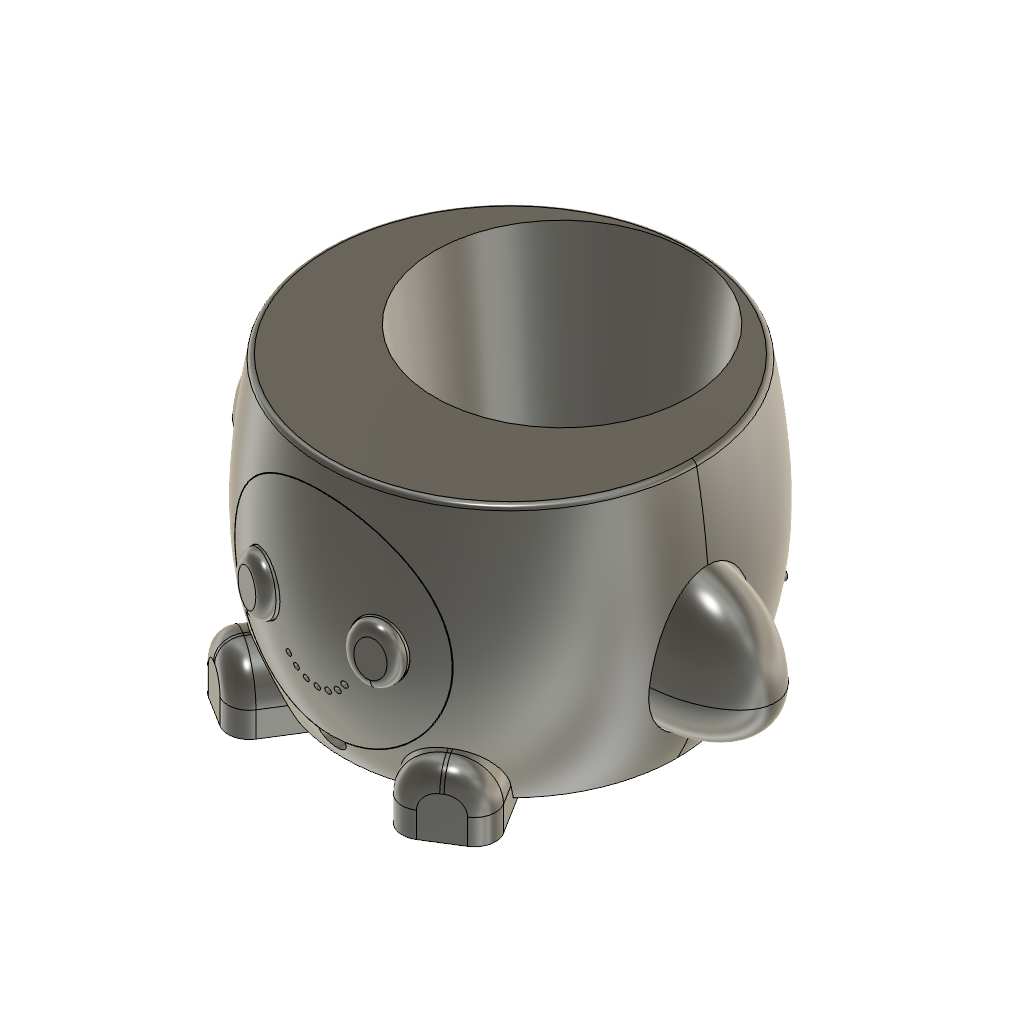
futamaru_pot (Autodesk Fusion 360 design; units mm, degrees)
Autodesk Fusion 360 part; units mm, degrees
(part 1 of 2)
sketch "スケッチ1" plane through (0, 0, 0) normal (0, 1, 0) x (1, 0, 0) in component "本体"
  spline S0 degree 5 poles (61, 0) (61.4755, -0.7477) (62.4092, -2.2714) (63.7579, -4.6416) (65.4521, -7.9718) (67.3928, -12.4202) (69.1495, -17.1541) (70.7118, -22.1673) (72.0655, -27.4438) (73.1935, -32.9563) (74.0795, -38.6683) (74.7115, -44.5354) (75.0851, -50.5067) (75.208, -56.5257) (75.1035, -62.5308) (74.8044, -68.4599) (74.349, -74.2534) (73.7756, -79.8585) (73.1181, -85.2326) (72.4013, -90.349) (71.6398, -95.1953) (71.0009, -98.8533) (70.5064, -101.4742) (70.1699, -103.1671) (70, -104) knots 0 0 0 0 0 0 0.05 0.1 0.15 0.2 0.25 0.3 0.35 0.4 0.45 0.5 0.55 0.6 0.65 0.7 0.75 0.8 0.85 0.9 0.95 1 1 1 1 1 1
  line L0 (0, 0) -> (61, 0)
  line L1 (70, -104) -> (0, -104)
  line L2 (0, -104) -> (0, 0)
  point P0 (70, -20)
  point P1 (75, -50)
  point P2 (73.5, -82)
  dimension "d76" = 61
  dimension "d77" = 70
  dimension "d78" = 20
  dimension "d79" = 75
  dimension "d80" = 50
  dimension "d81" = 73.5
  dimension "d82" = 82
  dimension "d83" = 70
  dimension "d84" = 104
  constraint horizontal L0
  constraint horizontal L1
  constraint vertical L2
  measures "d76" distance of L0.start S0.start
  measures "d77" horizontal distance of L0.start P0
  measures "d78" vertical distance of L0.start P0
  measures "d79" horizontal distance of L0.start P1
  measures "d80" vertical distance of L0.start P1
  measures "d81" horizontal distance of L0.start P2
  measures "d82" vertical distance of L0.start P2
  measures "d83" distance of L0.start S0.end
  measures "d84" distance of L0.start S0.end
revolve "本体 (1)" add sketch "スケッチ1" angle 360 about axis through (0, 0, 104) along (0, 0, -1) makes body 1 in component "本体"
chamfer "本体_底の面取り" distance 4 angle 45 1 edges at (-56.872, -22.0585, 0) tangent chain off on bodies 1 in component "本体"
fillet "本体_上の丸み" radius 2 1 edges at (-65.2629, -25.3131, 104) on bodies 1 in component "本体"
ref_plane "作業平面1" through (0, 0, 14) normal (0, 0, 1) x (1, 0, 0) in component "本体"
sketch "スケッチ2" plane through (0, 0, 14) normal (0, 0, 1) x (1, 0, 0) in component "本体"
  circle A0 centre (0, 19.5) radius 37
  line L0 (0, 0) -> (0, 10) construction
  dimension "d91" = 74
  dimension "d92" = 19.5
  constraint vertical L0
  constraint coincident A0.centre L0
  measures "d91" diameter of A0
  measures "d92" vertical distance of L0.start A0.centre
ref_plane "作業平面2" through (0, 0, 106) normal (0, 0, 1) x (1, 0, 0) in component "本体"
sketch "スケッチ3" plane through (0, 0, 106) normal (0, 0, 1) x (1, 0, 0) in component "本体"
  circle A0 centre (0, 19.5) radius 48.2444
  line L0 (0, 0) -> (0, 10) construction
  dimension "d95" = 96.4889
  dimension "d96" = 19.5
  constraint vertical L0
  constraint coincident A0.centre L0
  measures "d95" diameter of A0
  measures "d96" vertical distance of L0.start A0.centre
loft "鉢の穴" cut profiles "スケッチ2", "スケッチ3" section 1 section 2 bodies 1 in component "本体"
sketch "スケッチ4" plane through (0, 0, 14) normal (0, 0, 1) x (1, 0, 0) in component "本体"
  circle A0 centre (0, 41.5) radius 4
  line L0 (0, 0) -> (0, 10) construction
  circle A1 centre (-19.052, 8.5) radius 4
  circle A2 centre (19.052, 8.5) radius 4
  dimension "d97" = 8
  dimension "d98" = 41.5
  dimension "d99" = 8
  dimension "d100" = 19.052
  dimension "d101" = 8.5
  dimension "d102" = 8
  dimension "d103" = 19.052
  dimension "d104" = 8.5
  constraint vertical L0
  constraint coincident A0.centre L0
  measures "d97" diameter of A0
  measures "d98" vertical distance of L0.start A0.centre
  measures "d99" diameter of A1
  measures "d100" horizontal distance of L0.start A1.centre
  measures "d101" vertical distance of L0.start A1.centre
  measures "d102" diameter of A2
  measures "d103" horizontal distance of L0.start A2.centre
  measures "d104" vertical distance of L0.start A2.centre
extrude "鉢を浮かせる突起 (1)" add sketch "スケッチ4" along normal blind 3 bodies 1 in component "本体"
ref_plane "作業平面3" through (0, -90.5, 0) normal (0, 1, 0) x (0, 0, 1) in component "本体"
sketch "スケッチ5" plane through (0, -90.5, 0) normal (0, 1, 0) x (1, 0, 0) in component "本体"
  circle A0 centre (0, -54) radius 41.2
  line L0 (0, 0) -> (0, -10) construction
  dimension "d109" = 82.4
  dimension "d110" = 54
  constraint vertical L0
  constraint coincident A0.centre L0
  measures "d109" diameter of A0
  measures "d110" vertical distance of L0.start A0.centre
extrude "顔のふたの穴 (1)" cut sketch "スケッチ5" along normal blind 32 bodies 1 in component "本体"
ref_plane "作業平面4" through (0, -58.5, 0) normal (0, 1, 0) x (0, 0, 1) in component "本体"
sketch "スケッチ6" plane through (0, -58.5, 0) normal (0, 1, 0) x (1, 0, 0) in component "本体"
  circle A0 centre (0, -54) radius 39
  line L0 (0, 0) -> (0, -10) construction
  dimension "d115" = 78
  dimension "d116" = 54
  constraint vertical L0
  constraint coincident A0.centre L0
  measures "d115" diameter of A0
  measures "d116" vertical distance of L0.start A0.centre
extrude "部屋 (1)" cut sketch "スケッチ6" along normal blind 28 bodies 1 in component "本体"
sketch "スケッチ7" plane through (0, -90.5, 0) normal (0, 1, 0) x (1, 0, 0) in component "本体"
  circle A0 centre (0, -13) radius 5
  line L0 (0, 0) -> (0, -10) construction
  dimension "d119" = 10
  dimension "d120" = 13
  constraint vertical L0
  constraint coincident A0.centre L0
  measures "d119" diameter of A0
  measures "d120" vertical distance of L0.start A0.centre
extrude "指かけ (1)" cut sketch "スケッチ7" along normal blind 32 bodies 1 in component "本体"
sketch "スケッチ8" plane through (0, -58.5, 0) normal (0, 1, 0) x (1, 0, 0) in component "本体"
  circle A0 centre (34, -54) radius 6
  circle A1 centre (-34, -54) radius 6
  circle A2 centre (24, -30) radius 6
  circle A3 centre (-24, -30) radius 6
  dimension "d123" = 12
  dimension "d124" = 34
  dimension "d125" = 54
  dimension "d126" = 12
  dimension "d127" = 34
  dimension "d128" = 12
  dimension "d129" = 24
  dimension "d130" = 30
  dimension "d131" = 12
  dimension "d132" = 24
  dimension "d133" = 30
  measures "d123" diameter of A0
  measures "d124" horizontal distance of origin A0.centre
  measures "d125" vertical distance of origin A0.centre
  measures "d126" diameter of A1
  measures "d127" horizontal distance of origin A1.centre
  measures "d128" diameter of A2
  measures "d129" horizontal distance of origin A2.centre
  measures "d130" vertical distance of origin A2.centre
  measures "d131" diameter of A3
  measures "d132" horizontal distance of origin A3.centre
  measures "d133" vertical distance of origin A3.centre
extrude "磁石のボス (1)" add sketch "スケッチ8" along normal blind 5.5 bodies 1 in component "本体"
sketch "スケッチ9" plane through (0, -58.5, 0) normal (0, 1, 0) x (1, 0, 0) in component "本体"
  circle A0 centre (34, -54) radius 3.1
  circle A1 centre (-34, -54) radius 3.1
  circle A2 centre (24, -30) radius 3.1
  circle A3 centre (-24, -30) radius 3.1
  dimension "d136" = 6.2
  dimension "d137" = 34
  dimension "d138" = 54
  dimension "d139" = 6.2
  dimension "d140" = 34
  dimension "d141" = 6.2
  dimension "d142" = 24
  dimension "d143" = 30
  dimension "d144" = 6.2
  dimension "d145" = 24
  dimension "d146" = 30
  measures "d136" diameter of A0
  measures "d137" horizontal distance of origin A0.centre
  measures "d138" vertical distance of origin A0.centre
  measures "d139" diameter of A1
  measures "d140" horizontal distance of origin A1.centre
  measures "d141" diameter of A2
  measures "d142" horizontal distance of origin A2.centre
  measures "d143" vertical distance of origin A2.centre
  measures "d144" diameter of A3
  measures "d145" horizontal distance of origin A3.centre
  measures "d146" vertical distance of origin A3.centre
extrude "磁石の穴 (1)" cut sketch "スケッチ9" along normal blind 3.1 bodies 1 in component "本体"
ref_plane "作業平面5" through (0, 0, 29) normal (0, 0, 1) x (1, 0, 0) in component "本体"
sketch "スケッチ10" plane through (0, 0, 29) normal (0, 0, 1) x (1, 0, 0) in component "本体"
  line L0 (-13.5, -58.3) -> (13.5, -58.3)
  line L1 (13.5, -58.3) -> (13.5, -30.5)
  line L2 (13.5, -30.5) -> (-13.5, -30.5)
  line L3 (-13.5, -30.5) -> (-13.5, -58.3)
  dimension "d151" = 13.5
  dimension "d152" = 13.5
  dimension "d153" = 58.3
  dimension "d154" = 30.5
  measures "d151" horizontal distance of origin L0.start
  measures "d152" horizontal distance of origin L1.end
  measures "d153" vertical distance of origin L0.start
  measures "d154" vertical distance of origin L1.end
extrude "Voice Baseの台 (1)" add sketch "スケッチ10" against normal blind 20 bodies 1 in component "本体"
sketch "スケッチ11" plane through (0, 0, 29) normal (0, 0, 1) x (1, 0, 0) in component "本体"
  line L0 (-13.5, -58.3) -> (-12.3, -58.3)
  line L1 (-12.3, -58.3) -> (-12.3, -30.5)
  line L2 (-12.3, -30.5) -> (-13.5, -30.5)
  line L3 (-13.5, -30.5) -> (-13.5, -58.3)
  line L4 (12.3, -58.3) -> (13.5, -58.3)
  line L5 (13.5, -58.3) -> (13.5, -30.5)
  line L6 (13.5, -30.5) -> (12.3, -30.5)
  line L7 (12.3, -30.5) -> (12.3, -58.3)
  line L8 (-6, -34) -> (6, -34)
  line L9 (6, -34) -> (6, -30.5)
  line L10 (6, -30.5) -> (-6, -30.5)
  line L11 (-6, -30.5) -> (-6, -34)
  dimension "d157" = 13.5
  dimension "d158" = 12.3
  dimension "d159" = 58.3
  dimension "d160" = 30.5
  dimension "d161" = 12.3
  dimension "d162" = 13.5
  dimension "d163" = 30.5
  dimension "d164" = 6
  dimension "d165" = 6
  dimension "d166" = 34
  dimension "d167" = 30.5
  measures "d157" horizontal distance of origin L0.start
  measures "d158" horizontal distance of origin L1.end
  measures "d159" vertical distance of origin L0.start
  measures "d160" vertical distance of origin L1.end
  measures "d161" horizontal distance of origin L4.start
  measures "d162" horizontal distance of origin L5.end
  measures "d163" vertical distance of origin L5.end
  measures "d164" horizontal distance of origin L8.start
  measures "d165" horizontal distance of origin L9.end
  measures "d166" vertical distance of origin L8.start
  measures "d167" vertical distance of origin L9.end
extrude "Voice Baseの縁 (1)" add sketch "スケッチ11" along normal blind 4 bodies 1 in component "本体"
ref_plane "作業平面6" through (0, -30.5, 0) normal (0, 1, 0) x (0, 0, 1) in component "本体"
sketch "スケッチ12" plane through (0, -30.5, 0) normal (0, 1, 0) x (1, 0, 0) in component "本体"
  line L0 (12.1, -35.5) -> (13.3, -35.5)
  line L1 (13.3, -35.5) -> (13.3, -59.5)
  line L2 (13.3, -59.5) -> (12.1, -59.5)
  line L3 (12.1, -59.5) -> (12.1, -35.5)
  line L4 (31.7, -35.5) -> (32.9, -35.5)
  line L5 (32.9, -35.5) -> (32.9, -59.5)
  line L6 (32.9, -59.5) -> (31.7, -59.5)
  line L7 (31.7, -59.5) -> (31.7, -35.5)
  line L8 (12.1, -58.3) -> (32.9, -58.3)
  line L9 (32.9, -58.3) -> (32.9, -59.5)
  line L10 (32.9, -59.5) -> (12.1, -59.5)
  line L11 (12.1, -59.5) -> (12.1, -58.3)
  line L12 (12.1, -35.5) -> (15.75, -35.5)
  line L13 (15.75, -35.5) -> (15.75, -36.7)
  line L14 (15.75, -36.7) -> (12.1, -36.7)
  line L15 (12.1, -36.7) -> (12.1, -35.5)
  line L16 (29.25, -35.5) -> (32.9, -35.5)
  line L17 (32.9, -35.5) -> (32.9, -36.7)
  line L18 (32.9, -36.7) -> (29.25, -36.7)
  line L19 (29.25, -36.7) -> (29.25, -35.5)
  dimension "d172" = 12.1
  dimension "d173" = 13.3
  dimension "d174" = 35.5
  dimension "d175" = 59.5
  dimension "d176" = 31.7
  dimension "d177" = 32.9
  dimension "d178" = 59.5
  dimension "d179" = 32.9
  dimension "d180" = 58.3
  dimension "d181" = 59.5
  dimension "d182" = 15.75
  dimension "d183" = 36.7
  dimension "d184" = 29.25
  dimension "d185" = 32.9
  dimension "d186" = 36.7
  measures "d172" horizontal distance of origin L0.start
  measures "d173" horizontal distance of origin L1.end
  measures "d174" vertical distance of origin L0.start
  measures "d175" vertical distance of origin L1.end
  measures "d176" horizontal distance of origin L4.start
  measures "d177" horizontal distance of origin L5.end
  measures "d178" vertical distance of origin L5.end
  measures "d179" horizontal distance of origin L5.end
  measures "d180" vertical distance of origin L8.start
  measures "d181" vertical distance of origin L5.end
  measures "d182" horizontal distance of origin L13.end
  measures "d183" vertical distance of origin L13.end
  measures "d184" horizontal distance of origin L16.start
  measures "d185" horizontal distance of origin L17.end
  measures "d186" vertical distance of origin L17.end
extrude "XIAOの枠 (1)" add sketch "スケッチ12" against normal blind 5.2 bodies 1 in component "本体"
ref_plane "作業平面7" through (0, 0, -1) normal (0, 0, 1) x (1, 0, 0) in component "本体"
sketch "スケッチ13" plane through (0, 0, -1) normal (0, 0, 1) x (1, 0, 0) in component "本体"
  line L0 (15.5, -36.9) -> (29.5, -36.9)
  line L1 (29.5, -36.9) -> (29.5, -26.9)
  line L2 (29.5, -26.9) -> (15.5, -26.9)
  line L3 (15.5, -26.9) -> (15.5, -36.9)
  dimension "d191" = 15.5
  dimension "d192" = 29.5
  dimension "d193" = 36.9
  dimension "d194" = 26.9
  measures "d191" horizontal distance of origin L0.start
  measures "d192" horizontal distance of origin L1.end
  measures "d193" vertical distance of origin L0.start
  measures "d194" vertical distance of origin L1.end
extrude "USBケーブルの縦の穴 (1)" cut sketch "スケッチ13" along normal blind 46.3 bodies 1 in component "本体"
ref_plane "作業平面8" through (0, -31.9, 0) normal (0, 1, 0) x (0, 0, 1) in component "本体"
sketch "スケッチ14" plane through (0, -31.9, 0) normal (0, 1, 0) x (1, 0, 0) in component "本体"
  line L0 (19, 1) -> (26, 1)
  line L1 (26, 1) -> (26, -4.5)
  line L2 (26, -4.5) -> (22.5, -8)
  line L3 (22.5, -8) -> (19, -4.5)
  line L4 (19, -4.5) -> (19, 1)
extrude "USBケーブルの底の溝 (1)" cut sketch "スケッチ14" along normal blind 111.9 bodies 1 in component "本体"
ref_plane "作業平面1" through (0, -90.5, 0) normal (0, 1, 0) x (0, 0, 1) in component "顔のふた"
sketch "スケッチ1 (2)" plane through (0, -90.5, 0) normal (0, 1, 0) x (1, 0, 0) in component "顔のふた"
  circle A0 centre (0, -54) radius 41
  line L0 (0, 0) -> (0, -10) construction
  dimension "d203" = 82
  dimension "d204" = 54
  constraint vertical L0
  constraint coincident A0.centre L0
  measures "d203" diameter of A0
  measures "d204" vertical distance of L0.start A0.centre
extrude "顔のふた_外形 (1)" add sketch "スケッチ1 (2)" along normal blind 32 separate body makes body 2 in component "顔のふた"
sketch "スケッチ2 (2)" plane through (0, 0, 0) normal (0, 1, 0) x (1, 0, 0) in component "顔のふた"
  spline S0 degree 5 poles (61, 0) (61.4755, -0.7477) (62.4092, -2.2714) (63.7579, -4.6416) (65.4521, -7.9718) (67.3928, -12.4202) (69.1495, -17.1541) (70.7118, -22.1673) (72.0655, -27.4438) (73.1935, -32.9563) (74.0795, -38.6683) (74.7115, -44.5354) (75.0851, -50.5067) (75.208, -56.5257) (75.1035, -62.5308) (74.8044, -68.4599) (74.349, -74.2534) (73.7756, -79.8585) (73.1181, -85.2326) (72.4013, -90.349) (71.6398, -95.1953) (71.0009, -98.8533) (70.5064, -101.4742) (70.1699, -103.1671) (70, -104) knots 0 0 0 0 0 0 0.05 0.1 0.15 0.2 0.25 0.3 0.35 0.4 0.45 0.5 0.55 0.6 0.65 0.7 0.75 0.8 0.85 0.9 0.95 1 1 1 1 1 1
  line L0 (0, 0) -> (61, 0)
  line L1 (70, -104) -> (0, -104)
  line L2 (0, -104) -> (0, 0)
  point P0 (70, -20)
  point P1 (75, -50)
  point P2 (73.5, -82)
  constraint horizontal L0
  constraint horizontal L1
  constraint vertical L2
revolve "顔のふた_削り型 (1)" add sketch "スケッチ2 (2)" angle 360 about axis through (0, 0, 104) along (0, 0, -1) separate body makes body 3 in component "顔のふた"
chamfer "顔のふた_削り型_底の面取り" distance 4 angle 45 1 edges at (-56.872, -22.0585, 0) tangent chain off on bodies 3 in component "顔のふた"
fillet "顔のふた_削り型_上の丸み" radius 2 1 edges at (-65.2629, -25.3131, 104) on bodies 3 in component "顔のふた"
combine "顔のふた_本体の曲面で切る" operation intersect target body 2 tool bodies 3 in component "顔のふた"
ref_plane "作業平面2" through (0, -58.5, 0) normal (0, 1, 0) x (0, 0, 1) in component "顔のふた"
sketch "スケッチ3 (2)" plane through (0, -58.5, 0) normal (0, 1, 0) x (1, 0, 0) in component "顔のふた"
  line L0 (-14.1, -29.9) -> (14.1, -29.9)
  line L1 (14.1, -29.9) -> (14.1, -39.5)
  line L2 (14.1, -39.5) -> (-14.1, -39.5)
  line L3 (-14.1, -39.5) -> (-14.1, -29.9)
  dimension "d213" = 14.1
  dimension "d214" = 14.1
  dimension "d215" = 29.9
  dimension "d216" = 39.5
  measures "d213" horizontal distance of origin L0.start
  measures "d214" horizontal distance of origin L1.end
  measures "d215" vertical distance of origin L0.start
  measures "d216" vertical distance of origin L1.end
extrude "口の奥の音の部屋 (1)" cut sketch "スケッチ3 (2)" against normal blind 10.5 bodies 2 in component "顔のふた"
ref_plane "作業平面3" through (0, -68.5, 0) normal (0, 1, 0) x (0, 0, 1) in component "顔のふた"
sketch "スケッチ4 (2)" plane through (0, -68.5, 0) normal (0, 1, 0) x (1, 0, 0) in component "顔のふた"
  circle A0 centre (-10.5, -37.7) radius 1.2
  circle A1 centre (-7.7784, -34.505) radius 1.2
  circle A2 centre (-4.1344, -32.4227) radius 1.2
  circle A3 centre (0, -31.7) radius 1.2
  line L0 (0, 0) -> (0, -10) construction
  circle A4 centre (4.1344, -32.4227) radius 1.2
  circle A5 centre (7.7784, -34.505) radius 1.2
  circle A6 centre (10.5, -37.7) radius 1.2
  dimension "d221" = 2.4
  dimension "d222" = 10.5
  dimension "d223" = 37.7
  dimension "d224" = 2.4
  dimension "d225" = 7.7784
  dimension "d226" = 34.505
  dimension "d227" = 2.4
  dimension "d228" = 4.1344
  dimension "d229" = 32.4227
  dimension "d230" = 2.4
  dimension "d231" = 31.7
  dimension "d232" = 2.4
  dimension "d233" = 4.1344
  dimension "d234" = 32.4227
  dimension "d235" = 2.4
  dimension "d236" = 7.7784
  dimension "d237" = 34.505
  dimension "d238" = 2.4
  dimension "d239" = 10.5
  constraint vertical L0
  constraint coincident A3.centre L0
  measures "d221" diameter of A0
  measures "d222" horizontal distance of L0.start A0.centre
  measures "d223" vertical distance of L0.start A0.centre
  measures "d224" diameter of A1
  measures "d225" horizontal distance of L0.start A1.centre
  measures "d226" vertical distance of L0.start A1.centre
  measures "d227" diameter of A2
  measures "d228" horizontal distance of L0.start A2.centre
  measures "d229" vertical distance of L0.start A2.centre
  measures "d230" diameter of A3
  measures "d231" vertical distance of L0.start A3.centre
  measures "d232" diameter of A4
  measures "d233" horizontal distance of L0.start A4.centre
  measures "d234" vertical distance of L0.start A4.centre
  measures "d235" diameter of A5
  measures "d236" horizontal distance of L0.start A5.centre
  measures "d237" vertical distance of L0.start A5.centre
  measures "d238" diameter of A6
  measures "d239" horizontal distance of L0.start A6.centre
extrude "口 (1)" cut sketch "スケッチ4 (2)" against normal blind 20 bodies 2 in component "顔のふた"
sketch "スケッチ5 (2)" plane through (0, -58.5, 0) normal (0, 1, 0) x (1, 0, 0) in component "顔のふた"
  circle A0 centre (34, -54) radius 3.1
  circle A1 centre (-34, -54) radius 3.1
  circle A2 centre (24, -30) radius 3.1
  circle A3 centre (-24, -30) radius 3.1
  dimension "d242" = 6.2
  dimension "d243" = 34
  dimension "d244" = 54
  dimension "d245" = 6.2
  dimension "d246" = 34
  dimension "d247" = 6.2
  dimension "d248" = 24
  dimension "d249" = 30
  dimension "d250" = 6.2
  dimension "d251" = 24
  dimension "d252" = 30
  measures "d242" diameter of A0
  measures "d243" horizontal distance of origin A0.centre
  measures "d244" vertical distance of origin A0.centre
  measures "d245" diameter of A1
  measures "d246" horizontal distance of origin A1.centre
  measures "d247" diameter of A2
  measures "d248" horizontal distance of origin A2.centre
  measures "d249" vertical distance of origin A2.centre
  measures "d250" diameter of A3
  measures "d251" horizontal distance of origin A3.centre
  measures "d252" vertical distance of origin A3.centre
extrude "磁石の穴 (1)'" cut sketch "スケッチ5 (2)" against normal blind 3.1 bodies 2 in component "顔のふた"
ref_plane "作業平面1" through (0, -58.3, 0) normal (0, 1, 0) x (0, 0, 1) in component "参照部品（印刷しない）"
sketch "スケッチ1 (3)" plane through (0, -58.3, 0) normal (0, 1, 0) x (1, 0, 0) in component "参照部品（印刷しない）"
  line L0 (-12, -29) -> (12, -29)
  line L1 (12, -29) -> (12, -39)
  line L2 (12, -39) -> (-12, -39)
  line L3 (-12, -39) -> (-12, -29)
  dimension "d257" = 12
  dimension "d258" = 12
  dimension "d259" = 29
  dimension "d260" = 39
  measures "d257" horizontal distance of origin L0.start
  measures "d258" horizontal distance of origin L1.end
  measures "d259" vertical distance of origin L0.start
  measures "d260" vertical distance of origin L1.end
extrude "参照_Voice Base (1)" add sketch "スケッチ1 (3)" along normal blind 24 separate body makes body 4 in component "参照部品（印刷しない）"
ref_plane "作業平面2" through (0, 0, 39) normal (0, 0, 1) x (1, 0, 0) in component "参照部品（印刷しない）"
sketch "スケッチ2 (3)" plane through (0, 0, 39) normal (0, 0, 1) x (1, 0, 0) in component "参照部品（印刷しない）"
  line L0 (-3.78, -55.22) -> (8.92, -55.22)
  line L1 (8.92, -55.22) -> (8.92, -52.68)
  line L2 (8.92, -52.68) -> (-3.78, -52.68)
  line L3 (-3.78, -52.68) -> (-3.78, -55.22)
  dimension "d265" = 3.78
  dimension "d266" = 8.92
  dimension "d267" = 55.22
  dimension "d268" = 52.68
  measures "d265" horizontal distance of origin L0.start
  measures "d266" horizontal distance of origin L1.end
  measures "d267" vertical distance of origin L0.start
  measures "d268" vertical distance of origin L1.end
extrude "参照_Voice Baseのコネクタ (1)" add sketch "スケッチ2 (3)" along normal blind 14 separate body makes body 5 in component "参照部品（印刷しない）"
sketch "スケッチ3 (3)" plane through (0, 0, 39) normal (0, 0, 1) x (1, 0, 0) in component "参照部品（印刷しない）"
  line L0 (-1.24, -39.92) -> (8.92, -39.92)
  line L1 (8.92, -39.92) -> (8.92, -37.38)
  line L2 (8.92, -37.38) -> (-1.24, -37.38)
  line L3 (-1.24, -37.38) -> (-1.24, -39.92)
  dimension "d271" = 1.24
  dimension "d272" = 8.92
  dimension "d273" = 39.92
  dimension "d274" = 37.38
  measures "d271" horizontal distance of origin L0.start
  measures "d272" horizontal distance of origin L1.end
  measures "d273" vertical distance of origin L0.start
  measures "d274" vertical distance of origin L1.end
extrude "参照_Voice Baseのコネクタ (2)" add sketch "スケッチ3 (3)" along normal blind 14 separate body makes body 6 in component "参照部品（印刷しない）"
ref_plane "作業平面3" through (0, -33.5, 0) normal (0, 1, 0) x (0, 0, 1) in component "参照部品（印刷しない）"
sketch "スケッチ4 (3)" plane through (0, -33.5, 0) normal (0, 1, 0) x (1, 0, 0) in component "参照部品（印刷しない）"
  line L0 (13.6, -37) -> (31.4, -37)
  line L1 (31.4, -37) -> (31.4, -58)
  line L2 (31.4, -58) -> (13.6, -58)
  line L3 (13.6, -58) -> (13.6, -37)
  dimension "d279" = 13.6
  dimension "d280" = 31.4
  dimension "d281" = 37
  dimension "d282" = 58
  measures "d279" horizontal distance of origin L0.start
  measures "d280" horizontal distance of origin L1.end
  measures "d281" vertical distance of origin L0.start
  measures "d282" vertical distance of origin L1.end
extrude "参照_XIAO (1)" add sketch "スケッチ4 (3)" against normal blind 1.2 separate body makes body 7 in component "参照部品（印刷しない）"
sketch "スケッチ5 (3)" plane through (0, -33.5, 0) normal (0, 1, 0) x (1, 0, 0) in component "参照部品（印刷しない）"
  line L0 (16, -45) -> (29, -45)
  line L1 (29, -45) -> (29, -57)
  line L2 (29, -57) -> (16, -57)
  line L3 (16, -57) -> (16, -45)
  dimension "d285" = 16
  dimension "d286" = 29
  dimension "d287" = 45
  dimension "d288" = 57
  measures "d285" horizontal distance of origin L0.start
  measures "d286" horizontal distance of origin L1.end
  measures "d287" vertical distance of origin L0.start
  measures "d288" vertical distance of origin L1.end
extrude "参照_XIAOのシールド (1)" add sketch "スケッチ5 (3)" along normal blind 2.3 separate body makes body 8 in component "参照部品（印刷しない）"
sketch "スケッチ6 (2)" plane through (0, -33.5, 0) normal (0, 1, 0) x (1, 0, 0) in component "参照部品（印刷しない）"
  line L0 (18, -36) -> (27, -36)
  line L1 (27, -36) -> (27, -43.3)
  line L2 (27, -43.3) -> (18, -43.3)
  line L3 (18, -43.3) -> (18, -36)
  dimension "d291" = 18
  dimension "d292" = 27
  dimension "d293" = 36
  dimension "d294" = 43.3
  measures "d291" horizontal distance of origin L0.start
  measures "d292" horizontal distance of origin L1.end
  measures "d293" vertical distance of origin L0.start
  measures "d294" vertical distance of origin L1.end
extrude "参照_XIAOのUSB (1)" add sketch "スケッチ6 (2)" along normal blind 3.2 separate body makes body 9 in component "参照部品（印刷しない）"
ref_plane "作業平面4" through (0, -34.7, 0) normal (0, 1, 0) x (0, 0, 1) in component "参照部品（印刷しない）"
sketch "スケッチ7 (2)" plane through (0, -34.7, 0) normal (0, 1, 0) x (1, 0, 0) in component "参照部品（印刷しない）"
  line L0 (13.61, -38.61) -> (16.15, -38.61)
  line L1 (16.15, -38.61) -> (16.15, -56.39)
  line L2 (16.15, -56.39) -> (13.61, -56.39)
  line L3 (13.61, -56.39) -> (13.61, -38.61)
  dimension "d299" = 13.61
  dimension "d300" = 16.15
  dimension "d301" = 38.61
  dimension "d302" = 56.39
  measures "d299" horizontal distance of origin L0.start
  measures "d300" horizontal distance of origin L1.end
  measures "d301" vertical distance of origin L0.start
  measures "d302" vertical distance of origin L1.end
extrude "参照_XIAOのコネクタ (1)" add sketch "スケッチ7 (2)" against normal blind 16.5 separate body makes body 10 in component "参照部品（印刷しない）"
sketch "スケッチ8 (2)" plane through (0, -34.7, 0) normal (0, 1, 0) x (1, 0, 0) in component "参照部品（印刷しない）"
  line L0 (28.85, -38.61) -> (31.39, -38.61)
  line L1 (31.39, -38.61) -> (31.39, -56.39)
  line L2 (31.39, -56.39) -> (28.85, -56.39)
  line L3 (28.85, -56.39) -> (28.85, -38.61)
  dimension "d305" = 28.85
  dimension "d306" = 31.39
  dimension "d307" = 38.61
  dimension "d308" = 56.39
  measures "d305" horizontal distance of origin L0.start
  measures "d306" horizontal distance of origin L1.end
  measures "d307" vertical distance of origin L0.start
  measures "d308" vertical distance of origin L1.end
extrude "参照_XIAOのコネクタ (2)" add sketch "スケッチ8 (2)" against normal blind 16.5 separate body makes body 11 in component "参照部品（印刷しない）"
ref_plane "作業平面5" through (0, 0, 36) normal (0, 0, 1) x (1, 0, 0) in component "参照部品（印刷しない）"
sketch "スケッチ9 (2)" plane through (0, 0, 36) normal (0, 0, 1) x (1, 0, 0) in component "参照部品（印刷しない）"
  line L0 (16.25, -35.65) -> (28.75, -35.65)
  line L1 (28.75, -35.65) -> (28.75, -28.15)
  line L2 (28.75, -28.15) -> (16.25, -28.15)
  line L3 (16.25, -28.15) -> (16.25, -35.65)
  dimension "d313" = 16.25
  dimension "d314" = 28.75
  dimension "d315" = 35.65
  dimension "d316" = 28.15
  measures "d313" horizontal distance of origin L0.start
  measures "d314" horizontal distance of origin L1.end
  measures "d315" vertical distance of origin L0.start
  measures "d316" vertical distance of origin L1.end
extrude "参照_USBプラグ (1)" add sketch "スケッチ9 (2)" against normal blind 20 separate body makes body 12 in component "参照部品（印刷しない）"
ref_plane "作業平面6" through (0, 0, 16) normal (0, 0, 1) x (1, 0, 0) in component "参照部品（印刷しない）"
sketch "スケッチ10 (2)" plane through (0, 0, 16) normal (0, 0, 1) x (1, 0, 0) in component "参照部品（印刷しない）"
  circle A0 centre (22.5, -31.9) radius 2.25
  dimension "d321" = 4.5
  dimension "d322" = 22.5
  dimension "d323" = 31.9
  measures "d321" diameter of A0
  measures "d322" horizontal distance of origin A0.centre
  measures "d323" vertical distance of origin A0.centre
extrude "参照_ケーブル" add sketch "スケッチ10 (2)" against normal blind 7.5 separate body makes body 13 in component "参照部品（印刷しない）"
ref_plane "作業平面7" through (0, -26.9, 0) normal (0, 1, 0) x (0, 0, 1) in component "参照部品（印刷しない）"
sketch "スケッチ11 (2)" plane through (0, -26.9, 0) normal (0, 1, 0) x (1, 0, 0) in component "参照部品（印刷しない）"
  circle A0 centre (22.5, -3.5) radius 2.25
  dimension "d328" = 4.5
  dimension "d329" = 22.5
  dimension "d330" = 3.5
  measures "d328" diameter of A0
  measures "d329" horizontal distance of origin A0.centre
  measures "d330" vertical distance of origin A0.centre
extrude "参照_ケーブル (1)" add sketch "スケッチ11 (2)" along normal blind 106.9 separate body makes body 14 in component "参照部品（印刷しない）"
ref_plane "作業平面4" through (0, 0, 12.125) normal (0.292841, -0.956161, 0) x (0, 0, 1) in component "顔のふた"
ref_plane "作業平面5" through (21.7072, -70.8766, 12.125) normal (0.292841, -0.956161, 0) x (0, 0, 1) in component "顔のふた"
sketch "スケッチ6 (3)" plane through (21.7072, -70.8766, 0) normal (0.292841, -0.956161, 0) x (0, 0, 1) in component "顔のふた"
  ellipse E0 centre (54, 0) end of major axis (65.25, 0) minor radius 9.25
  line L0 (42.75, 0) -> (65.25, 0) construction
  line L1 (54, -9.25) -> (54, 9.25) construction
  constraint coincident E0 L0.start
  constraint coincident E0 L0.end
  constraint coincident E0 L1.start
  constraint coincident E0 L1.end
extrude "目の座面_右 (1)" cut sketch "スケッチ6 (3)" along normal blind 15 bodies 2 in component "顔のふた"
ref_plane "作業平面6" through (0, 0, 12.125) normal (-0.292841, -0.956161, 0) x (0, 0, 1) in component "顔のふた"
ref_plane "作業平面7" through (-21.7072, -70.8766, 12.125) normal (-0.292841, -0.956161, 0) x (0, 0, 1) in component "顔のふた"
sketch "スケッチ7 (3)" plane through (-21.7072, -70.8766, 0) normal (-0.292841, -0.956161, 0) x (0, 0, 1) in component "顔のふた"
  ellipse E0 centre (54, 0) end of major axis (65.25, 0) minor radius 9.25
  line L0 (42.75, 0) -> (65.25, 0) construction
  line L1 (54, -9.25) -> (54, 9.25) construction
  constraint coincident E0 L0.start
  constraint coincident E0 L0.end
  constraint coincident E0 L1.start
  constraint coincident E0 L1.end
extrude "目の座面_左 (1)" cut sketch "スケッチ7 (3)" along normal blind 15 bodies 2 in component "顔のふた"
sketch "スケッチ1 (4)" plane through (0, 0, 0) normal (0, 0, 1) x (1, 0, 0) in component "目"
  ellipse E0 centre (0, 0) end of major axis (0, 11) minor radius 9
  line L0 (0, -11) -> (0, 11) construction
  line L1 (9, 0) -> (-9, 0) construction
  constraint coincident E0 L0.start
  constraint coincident E0 L0.end
  constraint coincident E0 L1.start
  constraint coincident E0 L1.end
extrude "目 (1)" add sketch "スケッチ1 (4)" along normal blind 5.5 separate body makes body 15 in component "目"
fillet "目の丸み" radius 4 1 edges at (0, -11, 5.5) on bodies 15 in component "目"
ref_plane "作業平面9" through (66, 0, 0) normal (1, 0, 0) x (0, 1, 0) in component "本体"
sketch "スケッチ15" plane through (66, 0, 0) normal (1, 0, 0) x (0, 0, -1) in component "本体"
  ellipse E0 centre (-40, 0) end of major axis (-72.25, 0) minor radius 19.25
  line L0 (-7.75, 0) -> (-72.25, 0) construction
  line L1 (-40, 19.25) -> (-40, -19.25) construction
  ellipse E1 centre (-40, 0) end of major axis (-16.75, 0) minor radius 19.25
  line L2 (-63.25, 0) -> (-16.75, 0) construction
  line L3 (-40, 19.25) -> (-40, -19.25) construction
  line L4 (-40, -20.25) -> (-40, 20.25)
  constraint coincident E0 L0.start
  constraint coincident E0 L0.end
  constraint coincident E0 L1.start
  constraint coincident E0 L1.end
  constraint coincident E1 L2.start
  constraint coincident E1 L2.end
  constraint coincident E1 L1.start
  constraint coincident E1 L1.end
extrude "腕のくぼみ_右 (1)" cut sketch "スケッチ15" along normal blind 20 contours E0 E1 | E1 L4 | E1 L4 picked at (-64.038, 10.3067) bodies 1 in component "本体"
sketch "スケッチ16" plane through (66, 0, 0) normal (1, 0, 0) x (0, 0, -1) in component "本体"
  circle A0 centre (-34, 0) radius 3.15
  line L0 (0, 0) -> (-10, 0) construction
  circle A1 centre (-50, 0) radius 3.15
  dimension "d353" = 6.3
  dimension "d354" = 34
  dimension "d355" = 6.3
  dimension "d356" = 50
  constraint horizontal L0
  constraint coincident A0.centre L0
  constraint coincident L0 A1.centre
  measures "d353" diameter of A0
  measures "d354" horizontal distance of L0.start A0.centre
  measures "d355" diameter of A1
  measures "d356" horizontal distance of L0.start A1.centre
extrude "腕の穴_右 (1)" cut sketch "スケッチ16" against normal blind 8 bodies 1 in component "本体"
ref_plane "作業平面10" through (-66, 0, 0) normal (1, 0, 0) x (0, 1, 0) in component "本体"
sketch "スケッチ17" plane through (-66, 0, 0) normal (1, 0, 0) x (0, 0, -1) in component "本体"
  ellipse E0 centre (-40, 0) end of major axis (-72.25, 0) minor radius 19.25
  line L0 (-7.75, 0) -> (-72.25, 0) construction
  line L1 (-40, 19.25) -> (-40, -19.25) construction
  ellipse E1 centre (-40, 0) end of major axis (-16.75, 0) minor radius 19.25
  line L2 (-63.25, 0) -> (-16.75, 0) construction
  line L3 (-40, 19.25) -> (-40, -19.25) construction
  line L4 (-40, -20.25) -> (-40, 20.25)
  constraint coincident E0 L0.start
  constraint coincident E0 L0.end
  constraint coincident E0 L1.start
  constraint coincident E0 L1.end
  constraint coincident E1 L2.start
  constraint coincident E1 L2.end
  constraint coincident E1 L1.start
  constraint coincident E1 L1.end
extrude "腕のくぼみ_左 (1)" cut sketch "スケッチ17" against normal blind 20 contours E0 E1 | E1 L4 | E1 L4 picked at (-64.038, 10.3067) bodies 1 in component "本体"
sketch "スケッチ18" plane through (-66, 0, 0) normal (1, 0, 0) x (0, 0, -1) in component "本体"
  circle A0 centre (-34, 0) radius 3.15
  line L0 (0, 0) -> (-10, 0) construction
  circle A1 centre (-50, 0) radius 3.15
  dimension "d363" = 6.3
  dimension "d364" = 34
  dimension "d365" = 6.3
  dimension "d366" = 50
  constraint horizontal L0
  constraint coincident A0.centre L0
  constraint coincident L0 A1.centre
  measures "d363" diameter of A0
  measures "d364" horizontal distance of L0.start A0.centre
  measures "d365" diameter of A1
  measures "d366" horizontal distance of L0.start A1.centre
extrude "腕の穴_左 (1)" cut sketch "スケッチ18" along normal blind 8 bodies 1 in component "本体"
ref_plane "作業平面11" through (0, 0, 12.125) normal (0.529919, -0.848048, 0) x (0, 0, 1) in component "本体"
ref_plane "作業平面12" through (31.3432, -50.1597, 12.125) normal (0.529919, -0.848048, 0) x (0, 0, 1) in component "本体"
sketch "スケッチ19" plane through (31.3432, -50.1597, 0) normal (0.529919, -0.848048, 0) x (0, 0, 1) in component "本体"
  circle A0 centre (12, 0) radius 3.15
extrude "足の穴_右 (1)" cut sketch "スケッチ19" along normal blind 18 bodies 1 in component "本体"
ref_plane "作業平面13" through (0, 0, 12.125) normal (-0.529919, -0.848048, 0) x (0, 0, 1) in component "本体"
ref_plane "作業平面14" through (-31.3432, -50.1597, 12.125) normal (-0.529919, -0.848048, 0) x (0, 0, 1) in component "本体"
sketch "スケッチ20" plane through (-31.3432, -50.1597, 0) normal (-0.529919, -0.848048, 0) x (0, 0, 1) in component "本体"
  circle A0 centre (12, 0) radius 3.15
extrude "足の穴_左 (1)" cut sketch "スケッチ20" along normal blind 18 bodies 1 in component "本体"
sketch "スケッチ1 (5)" plane through (0, 0, 0) normal (0, 1, 0) x (1, 0, 0) in component "腕"
  ellipse E0 centre (66, -40) end of major axis (66, -72) minor radius 19
  line L0 (66, -8) -> (66, -72) construction
  line L1 (85, -40) -> (47, -40) construction
  ellipse E1 centre (66, -40) end of major axis (66, -17) minor radius 19
  line L2 (66, -63) -> (66, -17) construction
  line L3 (85, -40) -> (47, -40) construction
  line L4 (66, -40) -> (86, -40)
  line L5 (66, -7) -> (66, -73)
  point P0 (66, -40)
  constraint coincident E0 L0.start
  constraint coincident E0 L0.end
  constraint coincident E0 L1.start
  constraint coincident E0 L1.end
  constraint coincident E1 L2.start
  constraint coincident E1 L2.end
  constraint coincident E1 L1.start
  constraint coincident E1 L1.end
revolve "腕_卵" add sketch "スケッチ1 (5)" angle 360 about axis through (66, 0, 7) along (0, 0, 1) separate body contours E0 E1 L5 | E1 L4 L5 | E1 L4 L5 picked at (78.3178, -61.6765) makes body 16 in component "腕"
scale "腕_外へ伸ばす" factors (1.78947, 1, 1) about (66, 0, 40) bodies 16 in component "腕"
ref_plane "作業平面1" through (66, 0, 0) normal (1, 0, 0) x (0, 1, 0) in component "腕"
sketch "スケッチ2 (4)" plane through (66, 0, 0) normal (1, 0, 0) x (0, 0, -1) in component "腕"
  line L0 (42.5, -28.5) -> (-122.5, -28.5)
  line L1 (-122.5, -28.5) -> (-122.5, 28.5)
  line L2 (-122.5, 28.5) -> (42.5, 28.5)
  line L3 (42.5, 28.5) -> (42.5, -28.5)
  dimension "d387" = 28.5
  dimension "d388" = 28.5
  dimension "d389" = 42.5
  dimension "d390" = 122.5
  measures "d387" vertical distance of origin L0.start
  measures "d388" vertical distance of origin L1.end
  measures "d389" horizontal distance of origin L0.start
  measures "d390" horizontal distance of origin L1.end
extrude "腕の取り付け面 (1)" cut sketch "スケッチ2 (4)" against normal blind 39 bodies 16 in component "腕"
sketch "スケッチ3 (4)" plane through (66, 0, 0) normal (1, 0, 0) x (0, 0, -1) in component "腕"
  circle A0 centre (-34, 0) radius 3.15
  line L0 (0, 0) -> (-10, 0) construction
  circle A1 centre (-50, 0) radius 3.15
  dimension "d393" = 6.3
  dimension "d394" = 34
  dimension "d395" = 6.3
  dimension "d396" = 50
  constraint horizontal L0
  constraint coincident A0.centre L0
  constraint coincident L0 A1.centre
  measures "d393" diameter of A0
  measures "d394" horizontal distance of L0.start A0.centre
  measures "d395" diameter of A1
  measures "d396" horizontal distance of L0.start A1.centre
extrude "腕のピンの穴 (1)" cut sketch "スケッチ3 (4)" along normal blind 8 bodies 16 in component "腕"
sketch "スケッチ1 (6)" plane through (0, 0, 0) normal (0, 0, 1) x (1, 0, 0) in component "足"
  line L0 (55.1472, -15) -> (81.1472, -15)
  line L1 (81.1472, -15) -> (81.1472, 15)
  line L2 (81.1472, 15) -> (55.1472, 15)
  line L3 (55.1472, 15) -> (55.1472, -15)
  dimension "d399" = 55.1472
  dimension "d400" = 81.1472
  dimension "d401" = 15
  dimension "d402" = 15
  measures "d399" horizontal distance of origin L0.start
  measures "d400" horizontal distance of origin L1.end
  measures "d401" vertical distance of origin L0.start
  measures "d402" vertical distance of origin L1.end
extrude "足 (1)" add sketch "スケッチ1 (6)" along normal blind 24 separate body makes body 17 in component "足"
fillet "足のアーチ" radius 14.4 2 edges at (68.1472, -15, 24) (68.1472, 15, 24) on bodies 17 in component "足"
fillet "足のつま先" radius 8 25 edges at (81.1472, 10.7823, 19.7823) (81.1472, 15, 4.8) (81.1472, 0, 24) (81.1472, -10.7823, 19.7823) (81.1472, -15, 4.8) (81.1472, 0, 24) (81.1472, 10.7823, 19.7823) (81.1472, 15, 4.8) (81.1472, -10.7823, 19.7823) (81.1472, -15, 4.8) (81.1472, -10.7823, 19.7823) (81.1472, 0, 24) (81.1472, 10.7823, 19.7823) (81.1472, 15, 4.8) (81.1472, -15, 4.8) (81.1472, -15, 4.8) (81.1472, -10.7823, 19.7823) (81.1472, 0, 24) (81.1472, 10.7823, 19.7823) (81.1472, 15, 4.8) (81.1472, 15, 4.8) (81.1472, 10.7823, 19.7823) (81.1472, 0, 24) (81.1472, -10.7823, 19.7823) (81.1472, -15, 4.8) on bodies 17 in component "足"
sketch "スケッチ2 (5)" plane through (0, 0, 0) normal (0, 1, 0) x (1, 0, 0) in component "足"
  spline S0 degree 5 poles (61, 0) (61.4755, -0.7477) (62.4092, -2.2714) (63.7579, -4.6416) (65.4521, -7.9718) (67.3928, -12.4202) (69.1495, -17.1541) (70.7118, -22.1673) (72.0655, -27.4438) (73.1935, -32.9563) (74.0795, -38.6683) (74.7115, -44.5354) (75.0851, -50.5067) (75.208, -56.5257) (75.1035, -62.5308) (74.8044, -68.4599) (74.349, -74.2534) (73.7756, -79.8585) (73.1181, -85.2326) (72.4013, -90.349) (71.6398, -95.1953) (71.0009, -98.8533) (70.5064, -101.4742) (70.1699, -103.1671) (70, -104) knots 0 0 0 0 0 0 0.05 0.1 0.15 0.2 0.25 0.3 0.35 0.4 0.45 0.5 0.55 0.6 0.65 0.7 0.75 0.8 0.85 0.9 0.95 1 1 1 1 1 1
  line L0 (0, 0) -> (61, 0)
  line L1 (70, -104) -> (0, -104)
  line L2 (0, -104) -> (0, 0)
  point P0 (70, -20)
  point P1 (75, -50)
  point P2 (73.5, -82)
  constraint horizontal L0
  constraint horizontal L1
  constraint vertical L2
revolve "足_削り型 (1)" add sketch "スケッチ2 (5)" angle 360 about axis through (0, 0, 104) along (0, 0, -1) separate body makes body 18 in component "足"
chamfer "足_削り型_底の面取り" distance 4 angle 45 1 edges at (-56.872, -22.0585, 0) tangent chain off on bodies 18 in component "足"
fillet "足_削り型_上の丸み" radius 2 1 edges at (-65.2629, -25.3131, 104) on bodies 18 in component "足"
combine "足_根元を本体に沿わせる" operation cut target body 17 tool bodies 18 in component "足"
ref_plane "作業平面1" through (64.1472, 0, 0) normal (1, 0, 0) x (0, 1, 0) in component "足"
sketch "スケッチ3 (5)" plane through (64.1472, 0, 0) normal (1, 0, 0) x (0, 0, -1) in component "足"
  circle A0 centre (-12, 0) radius 3.15
  line L0 (0, 0) -> (-10, 0) construction
  dimension "d415" = 6.3
  dimension "d416" = 12
  constraint horizontal L0
  constraint coincident A0.centre L0
  measures "d415" diameter of A0
  measures "d416" horizontal distance of L0.start A0.centre
extrude "足のピンの穴 (1)" cut sketch "スケッチ3 (5)" along normal blind 11 bodies 17 in component "足"
component "本体" placed x (1, 0, 0) y (0, 1, 0) z (0, 0, 1) at (0, 0, 0)
component "顔のふた" placed x (1, 0, 0) y (0, 1, 0) z (0, 0, 1) at (0, 0, 0)
component "参照部品（印刷しない）" placed x (1, 0, 0) y (0, 1, 0) z (0, 0, 1) at (0, 0, 0)
component "目" placed x (0.956161, 0.292841, 0) y (0, 0, 1) z (0.292841, -0.956161, 0) at (21.7072, -70.8766, 54)
component "目" placed x (0.956161, -0.292841, 0) y (0, 0, 1) z (-0.292841, -0.956161, 0) at (-21.7072, -70.8766, 54)
component "腕" placed x (1, 0, 0) y (0, 1, 0) z (0, 0, 1) at (0, 0, 0)
component "腕" placed x (-1, 0, 0) y (0, -1, 0) z (0, 0, 1) at (0, 0, 0)
component "足" placed x (0.529919, -0.848048, 0) y (0.848048, 0.529919, 0) z (0, 0, 1) at (0, 0, 0)
component "足" placed x (-0.529919, -0.848048, 0) y (0.848048, -0.529919, 0) z (0, 0, 1) at (0, 0, 0)
equation "body_h = 104.0 mm" comment "本体の高さ（幅との比をチャムさんの案の 1.4 くらいにする）"
equation "r_bot = 61.0 mm" comment "底の半径"
equation "r_low = 70.0 mm" comment "下のふくらみの半径"
equation "z_low = 20.0 mm" comment "下のふくらみの高さ"
equation "r_belly = 75.0 mm" comment "いちばん太いところの半径"
equation "z_belly = 50.0 mm" comment "いちばん太いところの高さ（高さのほぼ真ん中）"
equation "r_sh = 73.5 mm" comment "肩の半径"
equation "z_sh = 82.0 mm" comment "肩の高さ"
equation "r_top = 70.0 mm" comment "上の縁の半径（鉢の穴の後ろの壁が薄くなりすぎない大きさ）"
equation "body_chamfer_bot = 4.0 mm" comment "底の角の面取り（45°。丸めると台のすぐ上が張り出してサポートが要るため面取りにする）"
equation "body_fillet_top = 2.0 mm" comment "上の縁の丸み（背面の壁が薄いので大きくできない）"
equation "face_y = 60.5 mm" comment "本体の中心から顔の基準面までの距離（部品の奥行きはここから測る）"
equation "pot_top_d = 96.0 mm" comment "鉢の穴の上の直径"
equation "pot_bot_d = 74.0 mm" comment "鉢の穴の底の直径"
equation "cav_off = 19.5 mm" comment "鉢の穴の中心を後ろへずらす量（前に電子部品の部屋を取るため）"
equation "floor_t = 14.0 mm" comment "底の厚さ（鉢の縁が本体の縁から沈みすぎないように上げる）"
equation "rib_d = 8.0 mm" comment "鉢を浮かせる突起の直径"
equation "rib_h = 3.0 mm" comment "鉢を浮かせる突起の高さ（受け皿の水から鉢底を離す）"
equation "rib_r = 22.0 mm" comment "突起を置く半径"
equation "comp_zc = 57.0 mm" comment "電子部品と顔の位置の基準の高さ"
equation "face_dz = -3.0 mm" comment "丸い部屋・顔の中心の高さ（comp_zc から）"
equation "comp_d = 78.0 mm" comment "部屋の内側の直径"
equation "comp_depth = 30.0 mm" comment "顔の面から部屋の奥の壁までの深さ"
equation "plate_d = 82.0 mm" comment "顔のふたの直径"
equation "plate_t = 2.0 mm" comment "基準面から顔のふたの背面（本体のくぼみの底）まで"
equation "plate_gap = 0.2 mm" comment "顔のふたと本体のすき間（片側）"
equation "notch_d = 10.0 mm" comment "顔のふたを外すための指かけの直径（あごの下）"
equation "mag_d = 6.2 mm" comment "磁石の穴の直径"
equation "mag_t = 3.1 mm" comment "磁石の穴の深さ"
equation "mag_boss_d = 12.0 mm" comment "本体側の磁石のボスの直径（部屋の壁につながる太さ）"
equation "mag_boss_len = 5.5 mm" comment "本体側の磁石のボスの長さ"
equation "eye_x = 22.0 mm" comment "目の中心・横（顔の中心から）"
equation "eye_dz = -3.0 mm" comment "目の中心の高さ（comp_zc から）。口の端との間を 3mm 以上あける"
equation "eye_w = 18.0 mm" comment "目の幅"
equation "eye_h = 22.0 mm" comment "目の高さ"
equation "eye_t = 5.5 mm" comment "目の厚さ"
equation "eye_round = 4.0 mm" comment "目のふちの丸み"
equation "eye_seat = 1.0 mm" comment "目を貼る平らな座面の、ふたの表面からの深さ（目の中心で）"
equation "eye_gap = 0.25 mm" comment "目の座面のすき間（片側）"
equation "mouth_w = 21.0 mm" comment "口の幅（両端の穴の中心どうし）。穴がみな Voice Base の前に来る幅にする"
equation "mouth_drop = 6.0 mm" comment "口の両端から、いちばん下までの深さ（大きいほど笑う）"
equation "mouth_dz = -19.3 mm" comment "口の両端の高さ（comp_zc から）"
equation "mouth_hole_d = 2.4 mm" comment "口の穴の直径（奥の部品が見えにくい細さ）"
equation "mouth_front = -8.5 mm" comment "ふたの裏の音の部屋の前の面（基準面から。マイナスは前）"
equation "vb_size = 24.0 mm" comment "Voice Base の幅・奥行き"
equation "vb_h = 10.0 mm" comment "Voice Base の箱の高さ（ピンを除く）"
equation "vb_z0 = -28.0 mm" comment "Voice Base の底の高さ（comp_zc から）。スピーカーの面を口の穴の奥に合わせる"
equation "vb_gap = 0.3 mm" comment "Voice Base の台のすき間（片側）"
equation "xiao_cx = 22.5 mm" comment "XIAO の中心・横"
equation "xiao_z0 = -20.0 mm" comment "XIAO の下の端（USB の口）の高さ（comp_zc から）"
equation "xiao_standoff = 3.0 mm" comment "奥の壁から基板の部品の面まで（部品とアンテナのコネクタの高さ。両面テープで貼る）"
equation "xiao_gap = 0.3 mm" comment "XIAO の枠のすき間（片側）"
equation "plug_w = 12.5 mm" comment "USB-C のプラグの根元（太いところ）の幅（ふつうのケーブルは 11〜12.5）"
equation "plug_t = 7.5 mm" comment "プラグの根元の厚さ"
equation "plug_len = 20.0 mm" comment "プラグの根元の長さ（これより長いとケーブルが溝へ曲がれない）"
equation "usb_ch_w = 14.0 mm" comment "プラグを通す縦の穴の幅"
equation "usb_ch_d = 10.0 mm" comment "プラグを通す縦の穴の奥行き"
equation "cable_d = 4.5 mm" comment "ケーブルの太さ"
equation "groove_w = 7.0 mm" comment "底の溝の幅"
equation "groove_h = 7.0 mm" comment "底の溝の深さ（屋根のてっぺんまで。屋根は 45°）"
equation "peg_d = 6.0 mm" comment "ダボピンの直径"
equation "peg_len = 15.0 mm" comment "ダボピンの長さ（本体と腕・足の穴の深さの合計より 1mm 短く）"
equation "peg_hole_d = 6.3 mm" comment "ダボピンの穴の直径"
equation "peg_hole_depth = 8.0 mm" comment "ダボピンの穴の深さ（本体側と、腕・足の側のそれぞれ）"
equation "arm_z = 40.0 mm" comment "腕のいちばん太いところの高さ（低めにして、ぶら下がった手に見せる）"
equation "arm_r = 19.0 mm" comment "腕の前後の半径"
equation "arm_top = 32.0 mm" comment "いちばん太いところから腕の上の端まで（上は細くとがる）"
equation "arm_bot = 23.0 mm" comment "いちばん太いところから腕の下の端まで"
equation "arm_out = 34.0 mm" comment "腕の取り付け面から外への出っ張り"
equation "arm_x0 = 66.0 mm" comment "腕の取り付け面（本体の中心から）。本体の側面をここまで卵形に掘り下げる"
equation "arm_gap = 0.25 mm" comment "腕のくぼみのすき間（片側）"
equation "foot_w = 30.0 mm" comment "足の幅（正面から見たアーチの幅）"
equation "foot_h = 24.0 mm" comment "足の高さ（これより高いと、正面から見て顔のふたにかかる）"
equation "foot_out = 14.0 mm" comment "足のつま先を本体の表面から前へ出す量"
equation "foot_toe = 8.0 mm" comment "つま先の丸み"
equation "d76 = r_bot"
equation "d77 = r_low"
equation "d78 = z_low"
equation "d79 = r_belly"
equation "d80 = z_belly"
equation "d81 = r_sh"
equation "d82 = z_sh"
equation "d83 = r_top"
equation "d84 = body_h"
equation "d86 = body_chamfer_bot"
equation "d88 = body_fillet_top"
equation "d89 = floor_t"
equation "d91 = pot_bot_d"
equation "d92 = cav_off"
equation "d93 = body_h + 2 mm"
equation "d95 = pot_top_d + ( pot_top_d - pot_bot_d ) * 2 mm / ( body_h - floor_t )"
equation "d96 = cav_off"
equation "d97 = rib_d"
equation "d98 = cav_off + rib_r"
equation "d99 = rib_d"
equation "d100 = -( -rib_r * 0.866 )"
equation "d101 = cav_off - rib_r / 2"
equation "d102 = rib_d"
equation "d103 = rib_r * 0.866"
equation "d104 = cav_off - rib_r / 2"
equation "d105 = rib_h"
equation "d107 = -face_y - 30 mm"
equation "d109 = plate_d + 2 * plate_gap"
equation "d110 = comp_zc + face_dz"
equation "d111 = 30 mm + plate_t"
equation "d113 = -face_y + plate_t"
equation "d115 = comp_d"
equation "d116 = comp_zc + face_dz"
equation "d117 = comp_depth - plate_t"
equation "d119 = notch_d"
equation "d120 = comp_zc + face_dz - plate_d / 2"
equation "d121 = 30 mm + plate_t"
equation "d123 = mag_boss_d"
equation "d125 = comp_zc + face_dz + 0.0 mm"
equation "d126 = mag_boss_d"
equation "d127 = -( -34.0 mm )"
equation "d128 = mag_boss_d"
equation "d130 = comp_zc + face_dz + -24.0 mm"
equation "d131 = mag_boss_d"
equation "d132 = -( -24.0 mm )"
equation "d133 = comp_zc + face_dz + -24.0 mm"
equation "d134 = mag_boss_len"
equation "d136 = mag_d"
equation "d138 = comp_zc + face_dz + 0.0 mm"
equation "d139 = mag_d"
equation "d140 = -( -34.0 mm )"
equation "d141 = mag_d"
equation "d143 = comp_zc + face_dz + -24.0 mm"
equation "d144 = mag_d"
equation "d145 = -( -24.0 mm )"
equation "d146 = comp_zc + face_dz + -24.0 mm"
equation "d147 = mag_t"
equation "d149 = comp_zc + vb_z0"
equation "d151 = -( ( 0 mm ) - ( vb_size + 2 * vb_gap + 2.4 mm ) / 2 )"
equation "d152 = ( 0 mm ) + ( vb_size + 2 * vb_gap + 2.4 mm ) / 2"
equation "d153 = -( ( ( ( -face_y + plate_t + 0.2 mm ) + ( -face_y + comp_depth ) ) / 2 ) - ( comp_depth - plate_t - 0.2 mm ) / 2 )"
equation "d154 = -( ( ( ( -face_y + plate_t + 0.2 mm ) + ( -face_y + comp_depth ) ) / 2 ) + ( comp_depth - plate_t - 0.2 mm ) / 2 )"
equation "d155 = -( 20 mm )"
equation "d157 = -( ( -( vb_size / 2 + vb_gap + 0.6 mm ) ) - ( 1.2 mm ) / 2 )"
equation "d158 = -( ( -( vb_size / 2 + vb_gap + 0.6 mm ) ) + ( 1.2 mm ) / 2 )"
equation "d159 = -( ( ( ( -face_y + plate_t + 0.2 mm ) + ( -face_y + comp_depth ) ) / 2 ) - ( comp_depth - plate_t - 0.2 mm ) / 2 )"
equation "d160 = -( ( ( ( -face_y + plate_t + 0.2 mm ) + ( -face_y + comp_depth ) ) / 2 ) + ( comp_depth - plate_t - 0.2 mm ) / 2 )"
equation "d161 = ( ( vb_size / 2 + vb_gap + 0.6 mm ) ) - ( 1.2 mm ) / 2"
equation "d162 = ( ( vb_size / 2 + vb_gap + 0.6 mm ) ) + ( 1.2 mm ) / 2"
equation "d163 = -( ( ( ( -face_y + plate_t + 0.2 mm ) + ( -face_y + comp_depth ) ) / 2 ) + ( comp_depth - plate_t - 0.2 mm ) / 2 )"
equation "d164 = -( ( 0 mm ) - ( 12 mm ) / 2 )"
equation "d165 = ( 0 mm ) + ( 12 mm ) / 2"
equation "d166 = -( ( ( ( ( -face_y + plate_t + 0.2 mm ) + vb_size + vb_gap ) + ( -face_y + comp_depth ) ) / 2 ) - ( ( -face_y + comp_depth ) - ( ( -face_y + plate_t + 0.2 mm ) + vb_size + vb_gap ) ) / 2 )"
equation "d167 = -( ( ( ( ( -face_y + plate_t + 0.2 mm ) + vb_size + vb_gap ) + ( -face_y + comp_depth ) ) / 2 ) + ( ( -face_y + comp_depth ) - ( ( -face_y + plate_t + 0.2 mm ) + vb_size + vb_gap ) ) / 2 )"
equation "d170 = -face_y + comp_depth"
equation "d172 = ( xiao_cx - ( 8.9 mm + xiao_gap + 0.6 mm ) ) - ( 1.2 mm ) / 2"
equation "d173 = ( xiao_cx - ( 8.9 mm + xiao_gap + 0.6 mm ) ) + ( 1.2 mm ) / 2"
equation "d174 = ( comp_zc + xiao_z0 + 10.5 mm ) - ( 21.0 mm + 2 * xiao_gap + 2.4 mm ) / 2"
equation "d175 = ( comp_zc + xiao_z0 + 10.5 mm ) + ( 21.0 mm + 2 * xiao_gap + 2.4 mm ) / 2"
equation "d176 = ( xiao_cx + ( 8.9 mm + xiao_gap + 0.6 mm ) ) - ( 1.2 mm ) / 2"
equation "d177 = ( xiao_cx + ( 8.9 mm + xiao_gap + 0.6 mm ) ) + ( 1.2 mm ) / 2"
equation "d178 = ( comp_zc + xiao_z0 + 10.5 mm ) + ( 21.0 mm + 2 * xiao_gap + 2.4 mm ) / 2"
equation "d179 = ( xiao_cx ) + ( 2 * ( 8.9 mm + xiao_gap + 1.2 mm ) ) / 2"
equation "d180 = ( comp_zc + xiao_z0 + 21.0 mm + xiao_gap + 0.6 mm ) - ( 1.2 mm ) / 2"
equation "d181 = ( comp_zc + xiao_z0 + 21.0 mm + xiao_gap + 0.6 mm ) + ( 1.2 mm ) / 2"